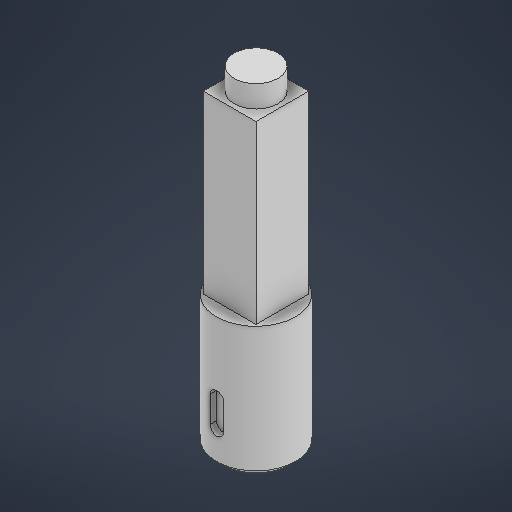
# Autodesk Inventor part: Eje
Saved by Autodesk Inventor 2026.2 (Build 302298000, 298)
## iProperties
Created: 2026-10-16
Part Number: Eje
Material: Genérico
Document SubType Name: Modeling
Designer: IFSP
Density: 1 g/cm^3
Appearance: Padrão
Author: IFSP
Autodesk Inventor part; units mm, degrees
ref_plane "YZ Plane" through (0, 0, 0) normal (1, 0, 0) x (0, 1, 0)
ref_plane "XZ Plane" through (0, 0, 0) normal (0, 1, 0) x (-1, 0, 0)
sketch "Esboço1" plane through (0, 0, 0) normal (0, 1, 0) x (-1, 0, 0)
  circle A0 centre (0, 0) radius 9
  dimension "d0" = 18
  constraints: 1 centre point, 1 coincident
  measures "d0" diameter of A0
extrude "Extrusão1" add sketch "Esboço1" along normal blind 30
sketch "Esboço2" plane through (0, 30, 0) normal (0, 1, 0) x (1, 0, 0)
  line L0 (-6, 6) -> (6, 6)
  line L1 (6, 6) -> (6, -6)
  line L2 (6, -6) -> (-6, -6)
  line L3 (-6, -6) -> (-6, 6)
  line L4 (-6, 6) -> (6, -6) construction
  line L5 (6, 6) -> (-6, -6) construction
  point P0 (0, 0)
  dimension "d3" = 12
  dimension "d4" = 12
  constraints: 12 end point, 2 midpoint, 2 parallel, 1 horizontal, 1 perpendicular
  measures "d3" distance of L1.end L2.end
  measures "d4" distance of L0.end L1.end
extrude "Extrusão2" add sketch "Esboço2" along normal blind 40
sketch "Esboço3" plane through (0, 70, 0) normal (0, 1, 0) x (1, 0, 0)
  circle A0 centre (0, 0) radius 5
  dimension "d7" = 10
  constraints: 1 centre point, 1 coincident
  measures "d7" diameter of A0
extrude "Extrusão3" add sketch "Esboço3" along normal blind 5
chamfer "Chanfro1" distance 1.5 angle 45 1 edges at (9, 0, 0) measured on face at (-2.2455, 0, -1.9894)
ref_plane "Plano de trabalho1" through (0, 0, 10.5) normal (0, 0, 1) x (1, 0, 0)
sketch "Esboço4" plane through (0, 0, 10.5) normal (0, 0, 1) x (1, 0, 0)
  line L0 (0, 0) -> (0, 8) construction
  line L1 (0, 8) -> (0, 14) construction
  line L2 (1.5, 8) -> (1.5, 14)
  line L3 (-1.5, 14) -> (-1.5, 8)
  arc A0 (-1.5, 8) -> (1.5, 8) centre (0, 8) ccw
  arc A1 (1.5, 14) -> (-1.5, 14) centre (0, 14) ccw
  point P0 (0, 11)
  dimension "d14" = 8
  dimension "d15" = 6
  dimension "d16" = 3
  constraints: 10 end point, 4 point on circle, 4 tangent, 2 centre point, 2 vertical, 1 midpoint, 1 parallel
  measures "d14" distance of L0.start L0.end
  measures "d15" distance of L0.end L1.end
  measures "d16" diameter of A1
extrude "Extrusão4" cut sketch "Esboço4" against normal blind 3
sketch "Esboço5" plane through (0, 0, 0) normal (0, -1, 0) x (1, 0, 0)
  point P0 (0, 0)
  point P1 (-0.1373, -0.2038)
hole "Furo1" at (-0.1373, 0, -0.2038) direction (0, 1, 0) diameter 15.2937 depth 20 tip angle 118 thread size "M18x2.5" class "6H" standard "ISO Metric profile"
